Autodesk Fusion 360 part; units mm, degrees
(part 2 of 2)
equation "port_wall = 3 mm" comment "engineering:E02; design_candidate"
equation "service_floor_y = 330 mm" comment "E08 internal50Ah battery, clear port channel and34L target; user allows quality/weight trade; design_candidate"
equation "brace_y = 240 mm" comment "E08 internal50Ah battery, clear port channel and34L target; user allows quality/weight trade; design_candidate"
equation "brace_z = 200 mm" comment "engineering:E02; design_candidate"
equation "brace_height = 20 mm" comment "engineering:E02; design_candidate"
equation "baffle_clearance = 0.5 mm" comment "engineering:E02; radial_manufacturing_allowance"
equation "amp_reserve_width = 110 mm" comment "engineering:E02; unverified_installation_reserve_not_board_dimension"
equation "amp_reserve_height = 110 mm" comment "engineering:E02; unverified_installation_reserve_not_board_dimension"
equation "amp_reserve_depth = 40 mm" comment "engineering:E02; unverified_installation_reserve_not_board_dimension"
equation "rear_cleat_width = 20 mm" comment "engineering:E03; prototype_candidate_not_structurally_validated"
equation "rear_cleat_depth = 20 mm" comment "engineering:E03; prototype_candidate_not_structurally_validated"
equation "lf_backing_outer_d = 280 mm" comment "engineering:E03; prototype_candidate_not_structurally_validated"
equation "lf_backing_thickness = 3 mm" comment "engineering:E03; prototype_candidate_not_structurally_validated"
equation "lf_bolt_clearance = 5.5 mm" comment "engineering:E03; prototype_candidate_not_structurally_validated"
equation "horn_bolt_clearance = 4.5 mm" comment "engineering:E03; prototype_candidate_not_structurally_validated"
equation "horn_bolt_pitch = 114 mm" comment "S50:drawing_me10v3; manufacturer_dimension"
equation "port_backing_relief = 1 mm" comment "engineering:E03; prototype_candidate_not_structurally_validated"
equation "rear_bolt_clearance = 5.5 mm" comment "engineering:E03; prototype_candidate_not_structurally_validated"
equation "rear_plate_width = 20 mm" comment "engineering:E03_assembly; candidate_verify_before_manufacture"
equation "rear_plate_length = 40 mm" comment "engineering:E03_assembly; candidate_verify_before_manufacture"
equation "rear_plate_thickness = 5 mm" comment "engineering:E03_assembly; candidate_verify_before_manufacture"
equation "rear_tap_pilot = 4.2 mm" comment "engineering:E03_assembly; candidate_verify_before_manufacture"
equation "rear_retainer_bore = 3 mm" comment "engineering:E03_assembly; candidate_verify_before_manufacture"
equation "rear_retainer_pitch = 24 mm" comment "engineering:E03_assembly; candidate_verify_before_manufacture"
equation "gasket_groove_width = 4 mm" comment "engineering:E03_assembly; candidate_verify_before_manufacture"
equation "gasket_groove_depth = 1 mm" comment "engineering:E03_assembly; candidate_verify_before_manufacture"
equation "gasket_edge_offset = 2 mm" comment "engineering:E03_assembly; candidate_verify_before_manufacture"
equation "lf_backing_inner_d = 220 mm" comment "engineering:E03_bearing_margin; candidate_clearance_model_only_verify_real_basket_before_cutting"
equation "port_x = 80 mm" comment "E08 left acoustic channel beside sealed rear-right battery bay; design_assumption"
equation "target_net = 34000000 mm^3" comment "report:p7"
equation "port_area = 6500 mm^2" comment "report:p7"
equation "port_length = 161.47860433 mm" comment "derived Helmholtz and equivalent-round end correction; prototype tune"
equation "lf_displacement = 600000 mm^3" comment "manufacturer occupied air volume, not solid clearance-envelope volume"
equation "horn_displacement = 150000 mm^3" comment "manufacturer horn volume"
equation "reinforcement_displacement = 1420463.1705 mm^3" comment "Python-derived E09 displacement"
equation "cleat_acoustic_displacement = 294400 mm^3" comment "Python-derived E09 displacement"
equation "backing_displacement = 70115.6356391 mm^3" comment "Python-derived E09 displacement"
equation "rear_fixing_displacement = 16924.3807921 mm^3" comment "Python-derived E09 displacement"
equation "battery_reserve = 9965424 mm^3" comment "E09 sealed battery bay excluded envelope"
equation "port_d = 90.9728368293 mm" comment "derived in Python; Fusion area-reference scaling workaround"
equation "service_z = 205.678225361 mm" comment "derived net-volume budget in Python; regenerate after dimensional changes"
equation "inner_width = width - 2 * wall" comment "E09 concept"
equation "inner_height = height - 2 * wall" comment "E09 concept"
equation "inner_depth = depth - 2 * wall" comment "E09 concept"
equation "port_outer_d = port_d + 2 * port_wall" comment "E09 concept"
equation "gross_internal = inner_width * inner_height * inner_depth" comment "E09 concept"
equation "port_displacement = PI / 4 * port_outer_d ^ 2 * ( port_length - 2 * wall )" comment "E09 concept"
equation "hf_displacement = PI / 4 * hf_diameter ^ 2 * hf_depth" comment "E09 concept"
equation "brace_displacement = inner_width * brace_height * wall" comment "E09 concept"
equation "service_reserve = inner_width * ( height - wall - service_floor_y ) * ( depth - wall - service_z )" comment "E09 concept"
equation "d76 = wall"
equation "d77 = height"
equation "d78 = depth"
equation "d82 = width - wall"
equation "d83 = wall"
equation "d84 = height"
equation "d85 = depth"
equation "d89 = wall"
equation "d90 = inner_width"
equation "d91 = wall"
equation "d92 = depth"
equation "d96 = wall"
equation "d97 = height - wall"
equation "d98 = inner_width"
equation "d99 = wall"
equation "d100 = depth"
equation "d104 = wall"
equation "d105 = wall"
equation "d106 = inner_width"
equation "d107 = inner_height"
equation "d108 = wall"
equation "d110 = depth - wall"
equation "d112 = wall"
equation "d113 = wall"
equation "d114 = inner_width"
equation "d115 = inner_height"
equation "d116 = wall"
equation "d120 = width / 2"
equation "d121 = lf_y"
equation "d122 = lf_cutout + 2 * baffle_clearance"
equation "d123 = wall"
equation "d127 = port_x"
equation "d128 = port_y"
equation "d129 = port_outer_d + 2 * baffle_clearance"
equation "d130 = wall"
equation "d134 = ( width - horn_cutout ) / 2"
equation "d135 = horn_y - horn_cutout / 2"
equation "d136 = horn_cutout"
equation "d137 = horn_cutout"
equation "d138 = wall"
equation "d140 = wall"
equation "d142 = wall"
equation "d143 = wall"
equation "d144 = inner_width"
equation "d145 = inner_height"
equation "d146 = wall"
equation "d148 = wall"
equation "d150 = width / 2"
equation "d151 = lf_y"
equation "d152 = lf_cutout + 2 * baffle_clearance"
equation "d153 = wall"
equation "d155 = wall"
equation "d157 = port_x"
equation "d158 = port_y"
equation "d159 = port_outer_d + 2 * baffle_clearance"
equation "d160 = wall"
equation "d162 = wall"
equation "d164 = ( width - horn_cutout ) / 2"
equation "d165 = horn_y - horn_cutout / 2"
equation "d166 = horn_cutout"
equation "d167 = horn_cutout"
equation "d168 = wall"
equation "d172 = width / 2 + lf_pcd / 2 * ( 1 )"
equation "d173 = lf_y + lf_pcd / 2 * ( 0 )"
equation "d174 = lf_bolt_clearance"
equation "d175 = wall"
equation "d179 = width / 2 + lf_pcd / 2 * ( 0.707106781186548 )"
equation "d180 = lf_y + lf_pcd / 2 * ( 0.707106781186548 )"
equation "d181 = lf_bolt_clearance"
equation "d182 = wall"
equation "d186 = width / 2 + lf_pcd / 2 * ( 0.000 )"
equation "d187 = lf_y + lf_pcd / 2 * ( 1 )"
equation "d188 = lf_bolt_clearance"
equation "d189 = wall"
equation "d193 = width / 2 + lf_pcd / 2 * ( -0.707106781186547 )"
equation "d194 = lf_y + lf_pcd / 2 * ( 0.707106781186548 )"
equation "d195 = lf_bolt_clearance"
equation "d196 = wall"
equation "d200 = width / 2 + lf_pcd / 2 * ( -1 )"
equation "d201 = lf_y + lf_pcd / 2 * ( 0.000 )"
equation "d202 = lf_bolt_clearance"
equation "d203 = wall"
equation "d207 = width / 2 + lf_pcd / 2 * ( -0.707106781186548 )"
equation "d208 = lf_y + lf_pcd / 2 * ( -0.707106781186547 )"
equation "d209 = lf_bolt_clearance"
equation "d210 = wall"
equation "d214 = width / 2 + lf_pcd / 2 * ( -0.000 )"
equation "d215 = lf_y + lf_pcd / 2 * ( -1 )"
equation "d216 = lf_bolt_clearance"
equation "d217 = wall"
equation "d221 = width / 2 + lf_pcd / 2 * ( 0.707106781186547 )"
equation "d222 = lf_y + lf_pcd / 2 * ( -0.707106781186548 )"
equation "d223 = lf_bolt_clearance"
equation "d224 = wall"
equation "d228 = width / 2 + ( -1 ) * horn_bolt_pitch / 2"
equation "d229 = horn_y + ( -1 ) * horn_bolt_pitch / 2"
equation "d230 = horn_bolt_clearance"
equation "d231 = wall"
equation "d235 = width / 2 + ( -1 ) * horn_bolt_pitch / 2"
equation "d236 = horn_y + ( 1 ) * horn_bolt_pitch / 2"
equation "d237 = horn_bolt_clearance"
equation "d238 = wall"
equation "d242 = width / 2 + ( 1 ) * horn_bolt_pitch / 2"
equation "d243 = horn_y + ( -1 ) * horn_bolt_pitch / 2"
equation "d244 = horn_bolt_clearance"
equation "d245 = wall"
equation "d249 = width / 2 + ( 1 ) * horn_bolt_pitch / 2"
equation "d250 = horn_y + ( 1 ) * horn_bolt_pitch / 2"
equation "d251 = horn_bolt_clearance"
equation "d252 = wall"
equation "d254 = wall"
equation "d256 = width / 2 + lf_pcd / 2 * ( 1 )"
equation "d257 = lf_y + lf_pcd / 2 * ( 0 )"
equation "d258 = lf_bolt_clearance"
equation "d259 = wall"
equation "d261 = wall"
equation "d263 = width / 2 + lf_pcd / 2 * ( 0.707106781186548 )"
equation "d264 = lf_y + lf_pcd / 2 * ( 0.707106781186548 )"
equation "d265 = lf_bolt_clearance"
equation "d266 = wall"
equation "d268 = wall"
equation "d270 = width / 2 + lf_pcd / 2 * ( 0.000 )"
equation "d271 = lf_y + lf_pcd / 2 * ( 1 )"
equation "d272 = lf_bolt_clearance"
equation "d273 = wall"
equation "d275 = wall"
equation "d277 = width / 2 + lf_pcd / 2 * ( -0.707106781186547 )"
equation "d278 = lf_y + lf_pcd / 2 * ( 0.707106781186548 )"
equation "d279 = lf_bolt_clearance"
equation "d280 = wall"
equation "d282 = wall"
equation "d284 = width / 2 + lf_pcd / 2 * ( -1 )"
equation "d285 = lf_y + lf_pcd / 2 * ( 0.000 )"
equation "d286 = lf_bolt_clearance"
equation "d287 = wall"
equation "d289 = wall"
equation "d291 = width / 2 + lf_pcd / 2 * ( -0.707106781186548 )"
equation "d292 = lf_y + lf_pcd / 2 * ( -0.707106781186547 )"
equation "d293 = lf_bolt_clearance"
equation "d294 = wall"
equation "d296 = wall"
equation "d298 = width / 2 + lf_pcd / 2 * ( -0.000 )"
equation "d299 = lf_y + lf_pcd / 2 * ( -1 )"
equation "d300 = lf_bolt_clearance"
equation "d301 = wall"
equation "d303 = wall"
equation "d305 = width / 2 + lf_pcd / 2 * ( 0.707106781186547 )"
equation "d306 = lf_y + lf_pcd / 2 * ( -0.707106781186548 )"
equation "d307 = lf_bolt_clearance"
equation "d308 = wall"
equation "d310 = wall"
equation "d312 = width / 2 + ( -1 ) * horn_bolt_pitch / 2"
equation "d313 = horn_y + ( -1 ) * horn_bolt_pitch / 2"
equation "d314 = horn_bolt_clearance"
equation "d315 = wall"
equation "d317 = wall"
equation "d319 = width / 2 + ( -1 ) * horn_bolt_pitch / 2"
equation "d320 = horn_y + ( 1 ) * horn_bolt_pitch / 2"
equation "d321 = horn_bolt_clearance"
equation "d322 = wall"
equation "d324 = wall"
equation "d326 = width / 2 + ( 1 ) * horn_bolt_pitch / 2"
equation "d327 = horn_y + ( -1 ) * horn_bolt_pitch / 2"
equation "d328 = horn_bolt_clearance"
equation "d329 = wall"
equation "d331 = wall"
equation "d333 = width / 2 + ( 1 ) * horn_bolt_pitch / 2"
equation "d334 = horn_y + ( 1 ) * horn_bolt_pitch / 2"
equation "d335 = horn_bolt_clearance"
equation "d336 = wall"
equation "d338 = 2 * wall"
equation "d340 = width / 2"
equation "d341 = lf_y"
equation "d342 = lf_backing_outer_d"
equation "d343 = lf_backing_inner_d"
equation "d344 = lf_backing_thickness"
equation "d346 = 2 * wall"
equation "d348 = width / 2 + lf_pcd / 2 * ( 1 )"
equation "d349 = lf_y + lf_pcd / 2 * ( 0 )"
equation "d350 = lf_bolt_clearance"
equation "d351 = lf_backing_thickness"
equation "d353 = 2 * wall"
equation "d355 = width / 2 + lf_pcd / 2 * ( 0.707106781186548 )"
equation "d356 = lf_y + lf_pcd / 2 * ( 0.707106781186548 )"
equation "d357 = lf_bolt_clearance"
equation "d358 = lf_backing_thickness"
equation "d360 = 2 * wall"
equation "d362 = width / 2 + lf_pcd / 2 * ( 0.000 )"
equation "d363 = lf_y + lf_pcd / 2 * ( 1 )"
equation "d364 = lf_bolt_clearance"
equation "d365 = lf_backing_thickness"
equation "d367 = 2 * wall"
equation "d369 = width / 2 + lf_pcd / 2 * ( -0.707106781186547 )"
equation "d370 = lf_y + lf_pcd / 2 * ( 0.707106781186548 )"
equation "d371 = lf_bolt_clearance"
equation "d372 = lf_backing_thickness"
equation "d374 = 2 * wall"
equation "d376 = width / 2 + lf_pcd / 2 * ( -1 )"
equation "d377 = lf_y + lf_pcd / 2 * ( 0.000 )"
equation "d378 = lf_bolt_clearance"
equation "d379 = lf_backing_thickness"
equation "d381 = 2 * wall"
equation "d383 = width / 2 + lf_pcd / 2 * ( -0.707106781186548 )"
equation "d384 = lf_y + lf_pcd / 2 * ( -0.707106781186547 )"
equation "d385 = lf_bolt_clearance"
equation "d386 = lf_backing_thickness"
equation "d388 = 2 * wall"
equation "d390 = width / 2 + lf_pcd / 2 * ( -0.000 )"
equation "d391 = lf_y + lf_pcd / 2 * ( -1 )"
equation "d392 = lf_bolt_clearance"
equation "d393 = lf_backing_thickness"
equation "d395 = 2 * wall"
equation "d397 = width / 2 + lf_pcd / 2 * ( 0.707106781186547 )"
equation "d398 = lf_y + lf_pcd / 2 * ( -0.707106781186548 )"
equation "d399 = lf_bolt_clearance"
equation "d400 = lf_backing_thickness"
equation "d402 = depth - wall - rear_cleat_depth"
equation "d404 = wall"
equation "d405 = wall"
equation "d406 = rear_cleat_width"
equation "d407 = inner_height"
equation "d408 = rear_cleat_depth"
equation "d410 = depth - wall - rear_cleat_depth"
equation "d412 = width - wall - rear_cleat_width"
equation "d413 = wall"
equation "d414 = rear_cleat_width"
equation "d415 = inner_height"
equation "d416 = rear_cleat_depth"
equation "d418 = depth - wall - rear_cleat_depth"
equation "d420 = wall + rear_cleat_width"
equation "d421 = wall"
equation "d422 = inner_width - 2 * rear_cleat_width"
equation "d423 = rear_cleat_width"
equation "d424 = rear_cleat_depth"
equation "d426 = depth - wall - rear_cleat_depth"
equation "d428 = wall + rear_cleat_width"
equation "d429 = height - wall - rear_cleat_width"
equation "d430 = inner_width - 2 * rear_cleat_width"
equation "d431 = rear_cleat_width"
equation "d432 = rear_cleat_depth"
equation "d434 = service_z"
equation "d436 = wall"
equation "d437 = service_floor_y + wall"
equation "d438 = inner_width"
equation "d439 = height - wall - service_floor_y - wall"
equation "d440 = wall"
equation "d442 = service_z"
equation "d444 = wall"
equation "d445 = service_floor_y"
equation "d446 = inner_width"
equation "d447 = wall"
equation "d448 = depth - wall - service_z"
equation "d450 = brace_z"
equation "d452 = wall"
equation "d453 = brace_y"
equation "d454 = inner_width"
equation "d455 = brace_height"
equation "d456 = wall"
equation "d460 = port_x"
equation "d461 = port_y"
equation "d462 = port_outer_d"
equation "d463 = port_d"
equation "d464 = port_length"
equation "d466 = -lf_flange"
equation "d468 = width / 2"
equation "d469 = lf_y"
equation "d470 = lf_outer"
equation "d471 = lf_cutout"
equation "d472 = lf_flange"
equation "d476 = width / 2"
equation "d477 = lf_y"
equation "d478 = lf_basket_d"
equation "d479 = lf_depth - lf_flange - lf_magnet_depth"
equation "d481 = width / 2"
equation "d482 = lf_y"
equation "d483 = lf_magnet_d"
equation "d484 = lf_depth - lf_flange - lf_magnet_depth"
equation "d486 = width / 2"
equation "d487 = lf_y"
equation "d488 = lf_magnet_d"
equation "d489 = lf_magnet_depth"
equation "d491 = -horn_flange"
equation "d493 = ( width - horn_width ) / 2"
equation "d494 = horn_y - horn_width / 2"
equation "d495 = horn_width"
equation "d496 = horn_width"
equation "d497 = horn_flange"
equation "d499 = -horn_flange"
equation "d501 = ( width - horn_cutout ) / 2"
equation "d502 = horn_y - horn_cutout / 2"
equation "d503 = horn_cutout"
equation "d504 = horn_cutout"
equation "d505 = horn_flange"
equation "d509 = ( width - horn_cutout ) / 2"
equation "d510 = horn_y - horn_cutout / 2"
equation "d511 = horn_cutout"
equation "d512 = horn_cutout"
equation "d513 = horn_depth - horn_flange"
equation "d515 = width / 2"
equation "d516 = horn_y"
equation "d517 = horn_throat"
equation "d518 = horn_depth - horn_flange"
equation "d520 = width / 2"
equation "d521 = horn_y"
equation "d522 = hf_diameter"
equation "d523 = hf_depth"
equation "d525 = service_z + wall + 10 mm"
equation "d527 = ( width - amp_reserve_width ) / 2"
equation "d528 = service_floor_y + wall + 10 mm"
equation "d529 = amp_reserve_width"
equation "d530 = amp_reserve_height"
equation "d531 = amp_reserve_depth"
named bodies: "Side_left", "Side_right", "Bottom", "Top", "Baffle", "Rear_removable", "Baffle_inner_lamination", "Steel_backing_ring", "Rear_cleat_left", "Rear_cleat_right", "Rear_cleat_bottom", "Rear_cleat_top", "Service_partition", "Service_floor", "Brace_lower", "Port_tube", "LF_flange_envelope", "Magnet_envelope", "Horn_flange_envelope", "DE10_cylinder_envelope", "Amp_space_reserve"
